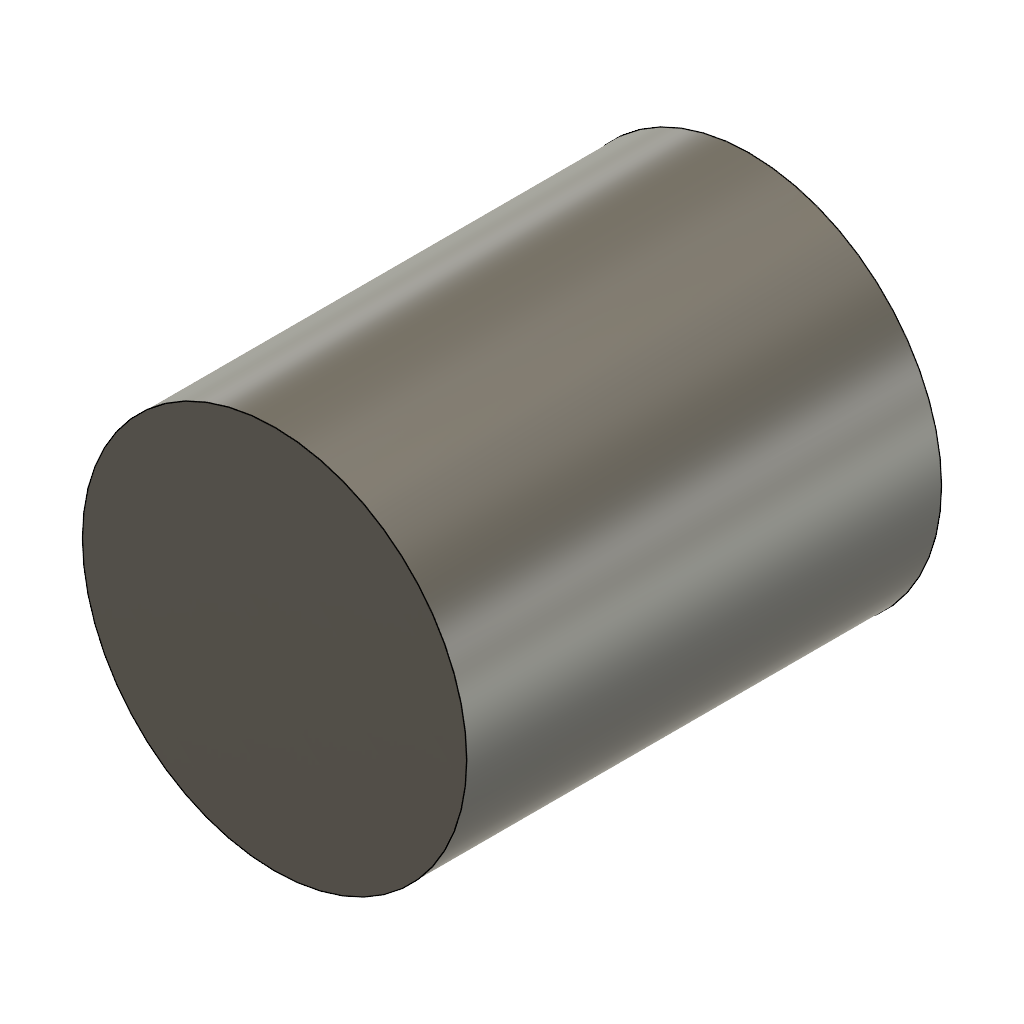
wide_first_small_edit_second (Autodesk Fusion 360 design; units mm, degrees)
part number: 2026-11-27-17-36-32-050
Autodesk Fusion 360 part; units mm, degrees
sketch "CircularProfile" plane through (0, 0, 0) normal (0, 0, 1) x (1, 0, 0)
  circle A0 centre (7, -11) radius 13
extrude "OffsetTwoSides" add sketch "CircularProfile" along normal blind 0.125 and the other way blind 32 from surface at 7
